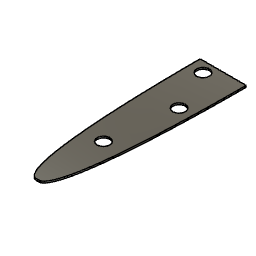
empreinte v1 (Autodesk Fusion 360 design; units mm, degrees)
Autodesk Fusion 360 part; units mm, degrees
sketch "Esquisse3" plane through (0, 0, 0) normal (0, 0, 1) x (1, 0, 0)
  line L0 (0, 0) -> (-14.5, 0)
  line L1 (0, -117) -> (16.349, -117)
  line L2 (16.349, -117) -> (16.349, -127.7234)
  line L3 (16.349, -127.7234) -> (0, -127.7234)
  line L4 (0, -127.7234) -> (0, -117)
  line L5 (-14.5, 0) -> (-14.5, -66.2729)
  line L6 (-14.5, -66.2729) -> (-10, -120)
  line L7 (-10, -120) -> (0, -117)
  spline S0 degree 3 poles (-14.5, 0) (-14.5, -66.2729) (-10, -120) (0, -117) knots 0 0 0 0 1 1 1 1
  spline S1 degree 3 poles (14.5, 0) (14.5, -66.2729) (10, -120) (0, -117) knots 0 0 0 0 1 1 1 1
  line L8 (14.5, 0) -> (14.5, -66.2729)
  line L9 (14.5, -66.2729) -> (10, -120)
  line L10 (10, -120) -> (0, -117)
  line L11 (0, 0) -> (14.5, 0)
  circle A0 centre (0, -75.5) radius 4
  circle A1 centre (5.7, -33.5) radius 4
  circle A2 centre (-6.1, -6.6) radius 4
  dimension "d4" = 14.5
  dimension "d5" = 117
  dimension "d6" = 8
  dimension "d7" = 8
  dimension "d8" = 8
  constraint coincident L0.start L11.start
  constraint horizontal L0
  constraint horizontal L1
  constraint vertical L2
  constraint horizontal L3
  constraint vertical L4
  measures "d4" distance of L0.start L0.end
  measures "d5" distance of L0.start L1.start
  measures "d6" diameter of A0
  measures "d7" diameter of A1
  measures "d8" diameter of A2
extrude "Extrusion1" add sketch "Esquisse3" along normal blind 1 contours L0 L1 S0 S1 L11
equation "d4 = ( 29 / 2 ) * 1 mm"
